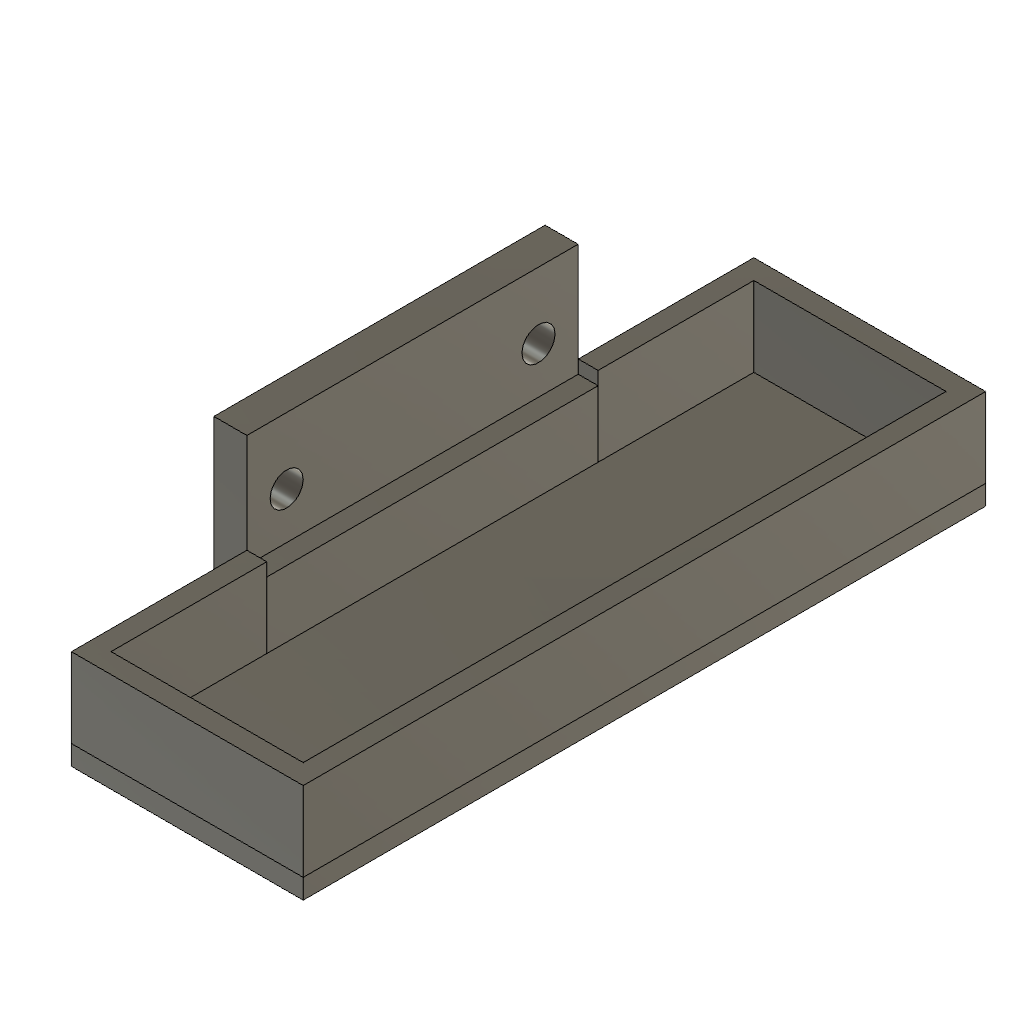
Big Motor Driver Holder (Autodesk Fusion 360 design; units mm, degrees)
Autodesk Fusion 360 part; units mm, degrees
sketch "Sketch1" plane through (0, 0, 0) normal (1, 0, 0) x (0, 1, 0)
  line L0 (25, -10) -> (-25, -10)
  line L1 (-25, -10) -> (-25, 10)
  line L2 (-25, 10) -> (25, 10)
  line L3 (25, 10) -> (25, -10)
  line L4 (25, -10) -> (-25, 10) construction
  line L5 (-25, -10) -> (25, 10) construction
  circle A0 centre (-19, 0) radius 2.5
  circle A1 centre (19, 0) radius 2.5
  line L6 (-25, -10) -> (25, -10)
  line L7 (25, -10) -> (25, -7)
  line L8 (25, -7) -> (-25, -7)
  line L9 (-25, -7) -> (-25, -10)
  dimension "d1" = 50
  dimension "d2" = 20
  dimension "d3" = 5
  dimension "d4" = 5
  dimension "d5" = 6
  dimension "d6" = 6
  dimension "d7" = 10
  dimension "d8" = 10
  dimension "d11" = 3
  constraint horizontal L0
  constraint perpendicular L0 L1
  constraint parallel L0 L2
  constraint parallel L1 L3
  constraint coincident L4 origin
  constraint coincident L5 origin
  constraint horizontal L6
  constraint vertical L7
  constraint horizontal L8
  constraint vertical L9
  measures "d1" distance of L1.end L2.end
  measures "d2" distance of L0.end L1.end
  measures "d3" diameter of A0
  measures "d4" diameter of A1
  measures "d5" distance of L1 A0.centre
  measures "d6" distance of L3 A1.centre
  measures "d7" distance of L2 A0.centre
  measures "d8" distance of L2 A1.centre
  measures "d11" distance of L0.end L8.end
extrude "Extrude1" add sketch "Sketch1" against normal blind 5 makes body 1
extrude "Extrude2" add sketch "Sketch1" along normal blind 3 contours L0 L1 L3 L6 L7 L8 L9 bodies 1
sketch "Sketch2" plane through (0, 0, -10) normal (0, 0, -1) x (1, 0, 0)
  line L0 (3, 25) -> (-5, 25)
  line L1 (-5, 25) -> (-5, -25)
  line L2 (-5, -25) -> (3, -25)
  line L3 (3, -25) -> (3, 25)
  line L4 (3, 25) -> (32, 25)
  line L5 (32, 25) -> (3, 25)
  line L6 (3, 25) -> (3, -25)
  line L7 (3, -25) -> (32, -25)
  line L8 (32, -25) -> (32, 25)
  line L9 (32, 25) -> (3, 25)
  line L10 (3, 25) -> (3, 48.5)
  line L11 (3, 48.5) -> (32, 48.5)
  line L12 (32, 48.5) -> (32, 25)
  line L13 (32, -25) -> (3, -25)
  line L14 (3, -25) -> (3, -48.5)
  line L15 (3, -48.5) -> (32, -48.5)
  line L16 (32, -48.5) -> (32, -25)
  line L17 (3, 48.5) -> (35, 48.5)
  line L18 (35, 48.5) -> (35, -51.5)
  line L19 (35, -51.5) -> (3, -51.5)
  line L20 (3, -51.5) -> (3, 48.5)
  line L21 (35, 48.5) -> (3, 48.5)
  line L22 (3, 48.5) -> (3, 51.5)
  line L23 (3, 51.5) -> (35, 51.5)
  line L24 (35, 51.5) -> (35, 48.5)
  line L25 (3, 51.5) -> (0, 51.5)
  line L26 (0, 51.5) -> (0, 25)
  line L27 (0, 25) -> (3, 25)
  line L28 (3, 25) -> (3, 51.5)
  line L29 (3, -51.5) -> (0, -51.5)
  line L30 (0, -51.5) -> (0, -25)
  line L31 (0, -25) -> (3, -25)
  line L32 (3, -25) -> (3, -51.5)
  dimension "d14" = 29
  dimension "d15" = 23.5
  dimension "d16" = 23.5
  dimension "d17" = 100
  dimension "d18" = 3
  dimension "d19" = 3
  dimension "d20" = 3
  constraint coincident L0.start L3.end
  constraint perpendicular L3 L4
  constraint horizontal L5
  constraint vertical L6
  constraint horizontal L7
  constraint vertical L8
  constraint coincident L2.end L3.start
  constraint horizontal L9
  constraint vertical L10
  constraint horizontal L11
  constraint vertical L12
  constraint horizontal L13
  constraint vertical L14
  constraint horizontal L15
  constraint vertical L16
  constraint horizontal L17
  constraint vertical L18
  constraint horizontal L19
  constraint vertical L20
  constraint horizontal L21
  constraint vertical L22
  constraint horizontal L23
  constraint vertical L24
  constraint horizontal L25
  constraint vertical L26
  constraint horizontal L27
  constraint vertical L28
  constraint horizontal L29
  constraint vertical L30
  constraint horizontal L31
  constraint vertical L32
  measures "d14" distance of L0.start L4.end
  measures "d15" distance of L4.end L11.end
  measures "d16" distance of L7.end L15.end
  measures "d17" distance of L10.end L19.end
  measures "d18" distance of L17.end L23.end
  measures "d19" distance of L22.end L25.end
  measures "d20" distance of L19.end L29.end
extrude "Extrude4" add 1 faces at (0.3333, 8.3333, -10) along direction (0, 0, -1) blind 10 on bodies 1 bodies 1
extrude "Extrude5" add sketch "Sketch2" along normal blind 3 from surface at 7 contours L3 L4 L5 L6 L7 L8 L9 L13 L20 | L4 L5 L9 L10 L11 L12 L17 L20 L21 L28 | L0 L10 L20 L22 L25 L26 L27 L28 | L2 L14 L20 L29 L30 L31 L32 | L7 L13 L14 L15 L16 L20 L32 | L8 L12 L15 L16 L17 L18 L19 L20 L21 L32 | L11 L17 L21 L22 L23 L24 L28 bodies 1
extrude "Extrude6" add sketch "Sketch2" along normal up to surface (7 mm away) and the other way blind 5 separate body contours L0 L10 L20 L22 L25 L26 L27 L28 | L2 L14 L20 L29 L30 L31 L32 | L8 L12 L15 L16 L17 L18 L19 L20 L21 L32 | L11 L17 L21 L22 L23 L24 L28 makes body 2
